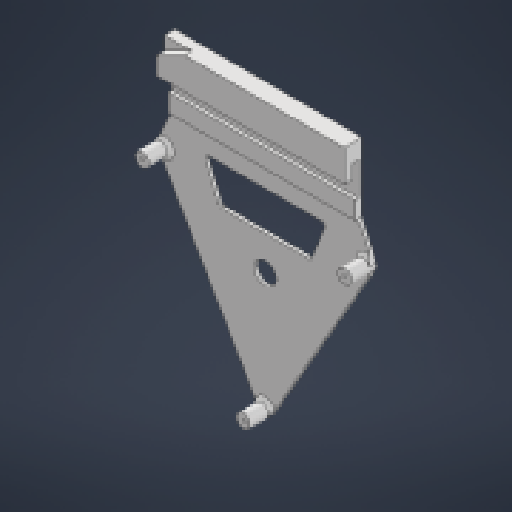
# Autodesk Inventor part: Rail
Saved by Autodesk Inventor 2027.1 (Build 311270010, 270A)
## iProperties
Created: 2026-11-11
Part Number: Rail
Material: 一般
Document SubType Name: Modeling
Designer: takuya
Density: 1 g/cm^3
Appearance: 既定
Author: takuya
Autodesk Inventor part; units mm, degrees
sketch "スケッチ1" plane through (0, 0, 0) normal (0, 0, 1) x (1, 0, 0)
  line L0 (-68, 1.5) -> (-48, 11.5) projected
  line L1 (-68, 1.5) -> (-68, -11.5) projected
  line L2 (-68, -11.5) -> (68, -11.5) projected
  line L3 (68, -11.5) -> (68, 11.5) projected
  line L4 (68, 11.5) -> (-48, 11.5) projected
  point P0 (0, 0)
ref_plane "作業平面1" through (-72.698523, -39.282573, -5.5) normal (0, 0, -1) x (0, 1, 0)
extrude "押し出し1" add sketch "スケッチ1" against normal up to surface (5.5 mm away)
sketch "スケッチ2" plane through (68, -11.5, -5.5) normal (0, 0, -1) x (-1, 0, 0)
  line L0 (0, 10) -> (0, 23) projected
  line L1 (0, 23) -> (136, 23) projected
  line L2 (136, 23) -> (136, 10) projected
  line L3 (136, 10) -> (0, 10) projected
  point P0 (68, 11.5)
ref_plane "作業平面2" through (-127.552123, -230.157444, -10.5) normal (0, 0, 1) x (0.9779387, 0.2088921, 0)
extrude "押し出し2" add sketch "スケッチ2" along normal up to surface (5 mm away)
sketch "スケッチ3" plane through (68, -1.5, -10.5) normal (0, 0, -1) x (-1, 0, 0)
  line L0 (11, -112.457906) -> (11, -72)
  line L1 (11, -72) -> (-16.784921, -72)
  line L2 (-16.784921, -72) -> (2.562553, -116.15496)
  line L3 (2.562553, -116.15496) -> (11, -112.457906)
  line L4 (78, -37) -> (58, -37)
  line L5 (58, -37) -> (58, -82.087122)
  arc A0 (78, -82.087122) -> (58, -82.087122) centre (68, -105) ccw
  line L6 (78, -82.087122) -> (78, -37)
  line L7 (38, -37) -> (18, -37)
  line L8 (18, -37) -> (18, -125.767478)
  line L9 (18, -125.767478) -> (38, -117.004035)
  line L10 (38, -117.004035) -> (38, -37)
  line L11 (118, -37) -> (98, -37)
  line L12 (98, -37) -> (98, -105)
  line L13 (98, -105) -> (118, -105)
  line L14 (118, -105) -> (118, -37)
  line L15 (94.658801, -147.746127) -> (125.088833, -147.746127)
  line L16 (125.088833, -147.746127) -> (119.16085, -112)
  line L17 (119.16085, -112) -> (102.294333, -112)
  line L18 (102.294333, -112) -> (94.658801, -147.746127)
  circle A1 centre (130.893082, -182.746127) radius 17.5
  circle A2 centre (51.393082, -182.746127) radius 17.5
  circle A3 centre (68, -105) radius 17.5
  arc A4 (-15.700427, -57) -> (-24.859738, -71.013355) centre (-15.700427, -67) ccw
  line L19 (-15.700427, -57) -> (0, -57)
  line L20 (0, -57) -> (0, 13)
  line L21 (0, 13) -> (136, 13)
  line L22 (136, 13) -> (136, -57)
  line L23 (136, -57) -> (156.08606, -57)
  arc A5 (166.047939, -67.872335) -> (156.08606, -57) centre (156.08606, -67) ccw
  line L24 (166.047939, -67.872335) -> (155.797779, -184.926965)
  arc A6 (130.893082, -207.746127) -> (155.797779, -184.926965) centre (130.893082, -182.746127) ccw
  line L25 (130.893082, -207.746127) -> (51.393082, -207.746127)
  arc A7 (28.494804, -192.779515) -> (51.393082, -207.746127) centre (51.393082, -182.746127) ccw
  line L26 (28.494804, -192.779515) -> (-24.859738, -71.013355)
  line L27 (0, -37) -> (136, -37)
  point P0 (68, 1.5)
  point P1 (18, -37)
  point P2 (58, -37)
  constraints: 2 end point, 2 point on line, 1 perpendicular
ref_plane "作業平面3" through (-127.552123, -230.157444, -13) normal (0, 0, -1) x (-0.2088921, 0.9779387, 0)
extrude "押し出し3" add sketch "スケッチ3" along normal up to surface (2.5 mm away) contours L4 L27 L7 L20 L21 L22 L11
sketch "スケッチ4" plane through (68, -1.5, -10.5) normal (0, 0, 1) x (1, 0, 0)
  line L0 (0, -37) -> (0, -24) projected
  line L1 (0, -24) -> (-136, -24) projected
  line L2 (-136, -24) -> (-136, -37) projected
  line L3 (-136, -37) -> (0, -37) projected
  point P0 (-68, 1.5)
ref_plane "作業平面4" through (-70.655687, -66.282573, -8) normal (0, 0, 1) x (1, 0, 0)
extrude "押し出し4" add sketch "スケッチ4" along normal up to surface (2.5 mm away)
sketch "スケッチ5" plane through (68, 11.5, -13) normal (0, 0, -1) x (-1, 0, 0)
  line L0 (136, -50) -> (0, -50)
  circle A0 centre (67.970661, -118.137245) radius 37.5
  line L1 (136, -50) -> (102.731964, -132.205005)
  line L2 (0, -50) -> (33.200734, -132.183674)
  circle A1 centre (67.966909, -118.154798) radius 8
  point P0 (68, -11.5)
  dimension "d8" = 75
  constraints: 4 end point, 2 point on circle, 2 tangent, 1 centre point
  measures "d8" diameter of A0
extrude "押し出し5" add sketch "スケッチ5" against normal up to surface (2.5 mm away) contours L1 A0 L2 L0 | A0 | A1
sketch "スケッチ6" plane through (-68, -38.5, -10.5) normal (0, 0, 1) x (1, 0, 0)
  ellipse E0 centre (68.029339, -68.137245) end of major axis (60.206091, -69.809608) minor radius 7.999778
  point P0 (68, 38.5)
  constraints: 1 other
extrude "押し出し6" cut sketch "スケッチ6" against normal up to surface (2.5 mm away)
sketch "スケッチ7" plane through (-68, -38.5, -10.5) normal (0, 0, 1) x (1, 0, 0)
  ellipse E0 centre (68.029339, -68.137245) end of major axis (60.206091, -69.809608) minor radius 7.999778
  arc A0 (33.268036, -82.205005) -> (102.799266, -82.183674) centre (68.029339, -68.137245) ccw
  line L0 (102.799266, -82.183674) -> (136, 0)
  line L1 (0, 0) -> (136, 0)
  line L2 (0, 0) -> (33.268036, -82.205005)
  circle A1 centre (68.029339, -68.137245) radius 25
  line L3 (136, 0) -> (0, 0)
  line L4 (0, 0) -> (0, -15)
  line L5 (0, -15) -> (136, -15)
  line L6 (136, -15) -> (136, 0)
  line L7 (112.5966, -15) -> (101.229657, -43.137245)
  line L8 (23.44199, -15) -> (34.829021, -43.137245)
  line L9 (34.829021, -43.137245) -> (101.229657, -43.137245)
  line L10 (102.799266, -82.183674) -> (136, 0)
  line L11 (0, 0) -> (33.268036, -82.205005)
  ellipse E1 centre (68.029339, -68.137245) end of major axis (60.206091, -69.809608) minor radius 7.999778
  point P0 (68, 38.5)
  point P1 (68.029339, -43.137245)
  dimension "d13" = 50
  dimension "d14" = 15
  constraints: 14 end point, 4 parallel, 2 horizontal, 2 point on line, 1 centre point, 1 coincident, 1 midpoint, 1 perpendicular, 1 tangent, 1 vertical alignment, 3 other
  measures "d13" diameter of A1
  measures "d14" distance of L4.end L3.end
extrude "押し出し7" cut sketch "スケッチ7" against normal up to surface (2.5 mm away) contours L5 L7 L9 L8
fillet "フィレット1" radius 2 4 edges at (33.2297, -81.6372, -11.75) (44.5966, -53.5, -11.75) (-44.558, -53.5, -11.75) (-33.171, -81.6372, -11.75)
sketch "スケッチ9" plane through (68, 11.5, -13) normal (0, 0, -1) x (-1, 0, 0)
  circle A0 centre (141.582821, -75.637245) radius 1.5
  arc A1 (146.410204, -76.939694) -> (142.868558, -70.805384) centre (141.582821, -75.637245) ccw
  arc A2 (64.429016, -206.666657) -> (71.512307, -206.666657) centre (67.970661, -203.137245) ccw
  circle A3 centre (67.970661, -203.137245) radius 1.5
  circle A4 centre (-5.641498, -75.637245) radius 1.5
  arc A5 (-6.927235, -70.805384) -> (-10.468881, -76.939694) centre (-5.641498, -75.637245) ccw
  line L0 (136, 0) -> (136, -50)
  line L1 (136, -50) -> (146.176064, -73.661867)
  line L2 (0, -50) -> (33.200734, -132.183674)
  line L3 (0, -50) -> (-10.2306, -73.652265)
  line L4 (146.644604, -76.869979) -> (72.300788, -205.637245)
  line L5 (-9.971625, -78.137245) -> (63.640534, -205.637245)
  circle A6 centre (141.582821, -75.637245) radius 5
  circle A7 centre (67.970661, -203.137245) radius 5
  circle A8 centre (-5.641498, -75.637245) radius 5
  line L6 (99.8228, -93.137245) -> (36.119415, -93.137245)
  arc A9 (34.265019, -91.886388) -> (36.119415, -93.137245) centre (36.119415, -91.137245) ccw
  line L7 (34.265019, -91.886388) -> (24.514004, -67.749143)
  arc A10 (26.3684, -65) -> (24.514004, -67.749143) centre (26.3684, -67) ccw
  line L8 (26.3684, -65) -> (109.591046, -65)
  arc A11 (111.444982, -67.750281) -> (109.591046, -65) centre (109.591046, -67) ccw
  line L9 (111.444982, -67.750281) -> (101.676736, -91.887525)
  arc A12 (99.8228, -93.137245) -> (101.676736, -91.887525) centre (99.8228, -91.137245) ccw
  ellipse E0 centre (67.970661, -118.137245) end of major axis (75.793909, -119.809608) minor radius 7.999778
  line L10 (0, 0) -> (136, 0)
  line L11 (0, -50) -> (0, 0)
  line L12 (0, -50) -> (33.200734, -132.183674)
  arc A13 (33.200734, -132.183674) -> (102.731964, -132.205005) centre (67.970661, -118.137245) ccw
  line L13 (102.731964, -132.205005) -> (136, -50)
  line L14 (136, 0) -> (136, -50)
  point P0 (68, -11.5)
  point P1 (33.200734, -132.183674)
  point P2 (145.912948, -78.137245)
extrude "押し出し8" add sketch "スケッチ9" against normal up to surface (2.5 mm away) contours A6 A1 | L4 A7 L5 A8 A5 L3 L2 A13 L13 L1 A1 A6 | A7 A2 | A8 A5
chamfer "面取り2" distance 2.5 angle 45 1 edges at (0, -38.5, -10.5)
sketch "スケッチ10" plane through (0.029339, -191.637245, -10.5) normal (0, 0, 1) x (1, 0, 0)
  circle A0 centre (73.612159, 127.5) radius 1.5
  circle A1 centre (-73.612159, 127.5) radius 1.5
  circle A2 centre (0, 0) radius 1.5
  arc A3 (-4.330127, -2.5) -> (4.330127, -2.5) centre (0, 0) ccw
  circle A4 centre (0, 0) radius 5
  circle A5 centre (-73.612159, 127.5) radius 5
  circle A6 centre (73.612159, 127.5) radius 5
  circle A7 centre (73.612159, 127.5) radius 1.25
  circle A8 centre (-73.612159, 127.5) radius 1.25
  circle A9 centre (0, 0) radius 1.25
  point P0 (-0.029339, 191.637245)
  point P1 (4.330127, -2.5)
  point P2 (-4.330127, -2.5)
  dimension "d27" = 10
  dimension "d28" = 10
  dimension "d29" = 10
  dimension "d30" = 2.5
  dimension "d31" = 2.5
  dimension "d32" = 2.5
  constraints: 6 centre point, 6 coincident
  measures "d27" diameter of A4
  measures "d28" diameter of A5
  measures "d29" diameter of A6
  measures "d30" diameter of A7
  measures "d31" diameter of A8
  measures "d32" diameter of A9
ref_plane "作業平面5" through (-78.582821, -196.637245, 5.274953) normal (0, 0, -1) x (0, 1, 0)
extrude "押し出し9" add sketch "スケッチ10" along normal up to surface (15.774953 mm away) contours A0 | A1 | A2 | A4 A3 | A5 | A6
chamfer "面取り3" distance 2.5 angle 45 4 edges at (0.0293, -186.6372, -10.5) (-72.5744, -59.24, -10.5) (-72.2887, -68.9669, -10.5) (68.6498, -63.849, -10.5)
sketch "スケッチ17" plane through (-69.075154, -41, -10.5) normal (0, 0, 1) x (1, 0, 0)
  line L0 (45.144457, -55.470578) -> (45.144457, -51.803912)
  line L1 (48.319883, -57.303912) -> (45.144457, -55.470578)
  line L2 (51.49531, -55.470578) -> (48.319883, -57.303912)
  line L3 (51.49531, -51.803912) -> (51.49531, -55.470578)
  line L4 (48.319883, -49.970578) -> (51.49531, -51.803912)
  line L5 (45.144457, -51.803912) -> (48.319883, -49.970578)
  circle A0 centre (48.319883, -53.637245) radius 5
  circle A1 centre (48.319883, -53.637245) radius 1.5
  line L6 (69.104493, -85.970578) -> (72.27992, -87.803912)
  line L7 (65.929067, -87.803912) -> (69.104493, -85.970578)
  line L8 (65.929067, -91.470578) -> (65.929067, -87.803912)
  line L9 (69.104493, -93.303912) -> (65.929067, -91.470578)
  line L10 (72.27992, -91.470578) -> (69.104493, -93.303912)
  line L11 (72.27992, -87.803912) -> (72.27992, -91.470578)
  circle A2 centre (69.104493, -89.637245) radius 5
  circle A3 centre (69.104493, -89.637245) radius 1.5
  line L12 (89.889103, -50.461818) -> (92.639103, -52.049532)
  line L13 (87.139103, -52.049532) -> (89.889103, -50.461818)
  line L14 (87.139103, -55.224958) -> (87.139103, -52.049532)
  line L15 (89.889103, -56.812671) -> (87.139103, -55.224958)
  line L16 (92.639103, -55.224958) -> (89.889103, -56.812671)
  line L17 (92.639103, -52.049532) -> (92.639103, -55.224958)
  circle A4 centre (89.889103, -53.637245) radius 1.5
  circle A5 centre (89.889103, -53.637245) radius 5
  point P0 (69.075154, 41)
  constraints: 36 end point, 6 centre point
extrude "押し出し14" add sketch "スケッチ17" along normal blind 0.5 contours A0 | A2 | A5
sketch "スケッチ19" plane through (0.029339, -130.637245, -10) normal (0, 0, 1) x (1, 0, 0)
  circle A0 centre (0, 0) radius 1.5
  ellipse E0 centre (0, 24) end of major axis (-7.823248, 22.327637) minor radius 7.999778
  line L0 (31.851246, 49) -> (-31.852138, 49)
  arc A1 (-33.706075, 50.249719) -> (-31.852138, 49) centre (-31.852138, 51) ccw
  line L1 (-33.706075, 50.249719) -> (-43.474321, 74.386964)
  arc A2 (-41.620385, 77.137245) -> (-43.474321, 74.386964) centre (-41.620385, 75.137245) ccw
  line L2 (-41.620385, 77.137245) -> (41.602261, 77.137245)
  arc A3 (43.456657, 74.388102) -> (41.602261, 77.137245) centre (41.602261, 75.137245) ccw
  line L3 (43.456657, 74.388102) -> (33.705642, 50.250857)
  arc A4 (31.851246, 49) -> (33.705642, 50.250857) centre (31.851246, 51) ccw
  arc A5 (75.981986, 73.615751) -> (75.147201, 59.158771) centre (73.612159, 66.5) ccw
  line L4 (75.981986, 73.615751) -> (69.052017, 89.637245)
  line L5 (-69.104493, 89.637245) -> (69.052017, 89.637245)
  line L6 (-69.104493, 89.637245) -> (-75.996863, 73.61078)
  arc A6 (-75.147201, 59.158771) -> (-75.996863, 73.61078) centre (-73.612159, 66.5) ccw
  line L7 (-75.147201, 59.158771) -> (-7.125212, -58.658771)
  arc A7 (7.125212, -58.658771) -> (-7.125212, -58.658771) centre (0, -61) ccw
  line L8 (7.125212, -58.658771) -> (75.147201, 59.158771)
  circle A8 centre (20.78461, 36) radius 5
  circle A9 centre (0, 0) radius 5
  circle A10 centre (-20.78461, 36) radius 5
  circle A11 centre (20.78461, 36) radius 1.5
  circle A12 centre (-20.78461, 36) radius 1.5
  point P0 (-0.029339, 130.637245)
  dimension "d65" = 3
  dimension "d66" = 3
  dimension "d67" = 3
  constraints: 3 centre point, 2 coincident, 1 other
  measures "d65" diameter of A0
  measures "d66" diameter of A11
  measures "d67" diameter of A12
extrude "押し出し16" add sketch "スケッチ19" along normal blind 1.5 contours A8 | A9 | A10
sketch "スケッチ20" plane through (68, 11.5, -13) normal (0, 0, -1) x (-1, 0, 0)
  line L0 (49.936052, -104.549532) -> (49.936052, -107.724958)
  line L1 (49.936052, -107.724958) -> (47.186052, -109.312671)
  line L2 (47.186052, -109.312671) -> (44.436052, -107.724958)
  line L3 (44.436052, -107.724958) -> (44.436052, -104.549532)
  line L4 (44.436052, -104.549532) -> (47.186052, -102.961818)
  line L5 (47.186052, -102.961818) -> (49.936052, -104.549532)
  line L6 (88.755271, -109.803912) -> (85.579845, -107.970578)
  line L7 (85.579845, -107.970578) -> (85.579845, -104.303912)
  line L8 (85.579845, -104.303912) -> (88.755271, -102.470578)
  line L9 (88.755271, -102.470578) -> (91.930698, -104.303912)
  line L10 (91.930698, -104.303912) -> (91.930698, -107.970578)
  line L11 (91.930698, -107.970578) -> (88.755271, -109.803912)
  line L12 (71.146088, -140.303912) -> (71.146088, -143.970578)
  line L13 (71.146088, -143.970578) -> (67.970661, -145.803912)
  line L14 (67.970661, -145.803912) -> (64.795235, -143.970578)
  line L15 (64.795235, -143.970578) -> (64.795235, -140.303912)
  line L16 (64.795235, -140.303912) -> (67.970661, -138.470578)
  line L17 (67.970661, -138.470578) -> (71.146088, -140.303912)
  point P0 (68, -11.5)
extrude "押し出し17" cut sketch "スケッチ20" against normal blind 2.5
sketch "スケッチ21" plane through (-69.075154, -41, -10.5) normal (0, 0, 1) x (1, 0, 0)
  ellipse E0 centre (69.104493, -65.637245) end of major axis (61.281246, -67.309608) minor radius 7.999778
  line L0 (100.955739, -40.637245) -> (37.252355, -40.637245)
  arc A0 (35.398418, -39.387525) -> (37.252355, -40.637245) centre (37.252355, -38.637245) ccw
  line L1 (35.398418, -39.387525) -> (25.630172, -15.250281)
  arc A1 (27.484108, -12.5) -> (25.630172, -15.250281) centre (27.484108, -14.5) ccw
  line L2 (27.484108, -12.5) -> (110.706754, -12.5)
  arc A2 (112.56115, -15.249143) -> (110.706754, -12.5) centre (110.706754, -14.5) ccw
  line L3 (112.56115, -15.249143) -> (102.810135, -39.386388)
  arc A3 (100.955739, -40.637245) -> (102.810135, -39.386388) centre (100.955739, -38.637245) ccw
  arc A4 (145.08648, -16.021493) -> (144.251694, -30.478474) centre (142.716652, -23.137245) ccw
  line L4 (145.08648, -16.021493) -> (138.15651, 0)
  line L5 (0, 0) -> (138.15651, 0)
  line L6 (0, 0) -> (-6.89237, -16.026465)
  arc A5 (-6.042708, -30.478474) -> (-6.89237, -16.026465) centre (-4.507666, -23.137245) ccw
  line L7 (-6.042708, -30.478474) -> (61.979281, -148.296016)
  arc A6 (76.229705, -148.296016) -> (61.979281, -148.296016) centre (69.104493, -150.637245) ccw
  line L8 (76.229705, -148.296016) -> (144.251694, -30.478474)
  circle A7 centre (89.889103, -53.637245) radius 5
  circle A8 centre (69.104493, -89.637245) radius 5
  circle A9 centre (48.319883, -53.637245) radius 5
  circle A10 centre (69.104493, -65.637245) radius 30
  line L9 (69.104493, -140.637245) -> (92.314247, -100.436771)
  line L10 (92.314247, -100.436771) -> (45.894739, -100.436771)
  line L11 (45.894739, -100.436771) -> (69.104493, -140.637245)
  line L12 (-6.042708, -30.478474) -> (61.979281, -148.296016)
  line L13 (76.229705, -148.296016) -> (144.251694, -30.478474)
  point P0 (69.075154, 41)
  dimension "d72" = 60
  dimension "d73" = 10
  dimension "d74" = 10
  constraints: 6 end point, 2 parallel, 1 centre point, 1 coincident, 1 horizontal, 1 vertical alignment, 1 other
  measures "d72" diameter of A10
  measures "d73" distance between parallel lines of L7 L11
  measures "d74" distance between parallel lines of L8 L9
extrude "押し出し18" cut sketch "スケッチ21" against normal blind 2.5 contours L11 L10 L9
fillet "フィレット2" radius 2 3 edges at (0.0293, -181.6372, -11.75) (-23.1804, -141.4368, -11.75) (23.2391, -141.4368, -11.75)
